Autodesk Fusion 360 part; units mm, degrees
(part 10 of 28)
  line L1869 (14.8547, 52.7364) -> (16.7828, 50.8083)
  line L1870 (16.7828, 50.8083) -> (30.5431, 50.8083)
  line L1871 (30.5431, 50.8083) -> (36.2449, 56.5101)
  line L1872 (36.2449, 56.5101) -> (36.2449, 62.5902)
  line L1873 (36.2449, 62.5902) -> (33.8607, 64.9744)
  line L1874 (33.8607, 64.9744) -> (31.4901, 64.9744)
  line L1875 (31.4901, 64.9744) -> (31.4117, 64.9795)
  line L1876 (31.4117, 64.9795) -> (31.2605, 65.02)
  line L1877 (31.2605, 65.02) -> (31.1248, 65.0984)
  line L1878 (31.1248, 65.0984) -> (31.0658, 65.1501)
  line L1879 (31.0658, 65.1501) -> (28.9704, 67.2455)
  line L1880 (28.9704, 67.2455) -> (28.9187, 67.3045)
  line L1881 (28.9187, 67.3045) -> (28.8404, 67.4401)
  line L1882 (28.8404, 67.4401) -> (28.7998, 67.5914)
  line L1883 (28.7998, 67.5914) -> (28.7947, 67.6697)
  line L1884 (28.7947, 67.6697) -> (28.7947, 69.2413)
  line L1885 (28.7947, 69.2413) -> (28.7998, 69.3196)
  line L1886 (28.7998, 69.3196) -> (28.8404, 69.4709)
  line L1887 (28.8404, 69.4709) -> (28.8416, 69.473)
  line L1888 (28.8416, 69.473) -> (28.8416, 73.4443)
  line L1889 (28.8416, 73.4443) -> (28.8072, 73.4673)
  line L1890 (28.8072, 73.4673) -> (28.6686, 73.6059)
  line L1891 (28.6686, 73.6059) -> (28.5597, 73.7689)
  line L1892 (28.5597, 73.7689) -> (28.4847, 73.95)
  line L1893 (28.4847, 73.95) -> (28.4464, 74.1423)
  line L1894 (28.4464, 74.1423) -> (28.4416, 74.2403)
  line L1895 (28.4416, 74.2403) -> (28.4416, 75.4403)
  line L1896 (28.4416, 75.4403) -> (28.4464, 75.5383)
  line L1897 (28.4464, 75.5383) -> (28.4847, 75.7306)
  line L1898 (28.4847, 75.7306) -> (28.5597, 75.9117)
  line L1899 (28.5597, 75.9117) -> (28.6686, 76.0747)
  line L1900 (28.6686, 76.0747) -> (28.8072, 76.2133)
  line L1901 (28.8072, 76.2133) -> (28.9702, 76.3222)
  line L1902 (28.9702, 76.3222) -> (29.1513, 76.3972)
  line L1903 (29.1513, 76.3972) -> (29.3436, 76.4355)
  line L1904 (29.3436, 76.4355) -> (29.5396, 76.4355)
  line L1905 (29.5396, 76.4355) -> (29.7319, 76.3972)
  line L1906 (29.7319, 76.3972) -> (29.913, 76.3222)
  line L1907 (29.913, 76.3222) -> (30.0101, 76.2573)
  line L1908 (30.0101, 76.2573) -> (32.9677, 79.2149)
  line L1909 (32.9677, 79.2149) -> (32.9677, 83.0947)
  line L1910 (32.9677, 83.0947) -> (32.9146, 83.1217)
  line L1911 (32.9146, 83.1217) -> (32.7559, 83.237)
  line L1912 (32.7559, 83.237) -> (32.6172, 83.3757)
  line L1913 (32.6172, 83.3757) -> (32.5019, 83.5344)
  line L1914 (32.5019, 83.5344) -> (32.4128, 83.7092)
  line L1915 (32.4128, 83.7092) -> (32.3522, 83.8957)
  line L1916 (32.3522, 83.8957) -> (32.3215, 84.0895)
  line L1917 (32.3215, 84.0895) -> (32.3177, 84.1875)
  line L1918 (32.3177, 84.1875) -> (32.3177, 84.6875)
  line L1919 (32.3177, 84.6875) -> (32.3215, 84.7856)
  line L1920 (32.3215, 84.7856) -> (32.3522, 84.9793)
  line L1921 (32.3522, 84.9793) -> (32.4128, 85.1659)
  line L1922 (32.4128, 85.1659) -> (32.5019, 85.3407)
  line L1923 (32.5019, 85.3407) -> (32.6172, 85.4993)
  line L1924 (32.6172, 85.4993) -> (32.7559, 85.638)
  line L1925 (32.7559, 85.638) -> (32.9146, 85.7533)
  line L1926 (32.9146, 85.7533) -> (33.0893, 85.8424)
  line L1927 (33.0893, 85.8424) -> (33.2759, 85.903)
  line L1928 (33.2759, 85.903) -> (33.4696, 85.9337)
  line L1929 (33.4696, 85.9337) -> (33.6658, 85.9337)
  line L1930 (33.6658, 85.9337) -> (33.8595, 85.903)
  line L1931 (68.7845, 85.903) -> (68.971, 85.8424)
  line L1932 (68.971, 85.8424) -> (69.1458, 85.7533)
  line L1933 (69.1458, 85.7533) -> (69.3045, 85.638)
  line L1934 (69.3045, 85.638) -> (69.4432, 85.4993)
  line L1935 (69.4432, 85.4993) -> (69.5585, 85.3407)
  line L1936 (69.5585, 85.3407) -> (69.6475, 85.1659)
  line L1937 (69.6475, 85.1659) -> (69.7082, 84.9793)
  line L1938 (69.7082, 84.9793) -> (69.7388, 84.7856)
  line L1939 (69.7388, 84.7856) -> (69.7427, 84.6875)
  line L1940 (69.7427, 84.6875) -> (69.7427, 84.1875)
  line L1941 (69.7427, 84.1875) -> (69.7388, 84.0895)
  line L1942 (69.7388, 84.0895) -> (69.7082, 83.8957)
  line L1943 (69.7082, 83.8957) -> (69.6475, 83.7092)
  line L1944 (69.6475, 83.7092) -> (69.5585, 83.5344)
  line L1945 (69.5585, 83.5344) -> (69.4432, 83.3757)
  line L1946 (69.4432, 83.3757) -> (69.3045, 83.237)
  line L1947 (69.3045, 83.237) -> (69.1458, 83.1217)
  line L1948 (69.1458, 83.1217) -> (69.0927, 83.0947)
  line L1949 (69.0927, 83.0947) -> (69.0927, 78.9664)
  line L1950 (69.0927, 78.9664) -> (69.0876, 78.8881)
  line L1951 (69.0876, 78.8881) -> (69.047, 78.7368)
  line L1952 (69.047, 78.7368) -> (68.9687, 78.6011)
  line L1953 (68.9687, 78.6011) -> (68.917, 78.5421)
  line L1954 (68.917, 78.5421) -> (65.3666, 74.9918)
  line L1955 (65.3666, 74.9918) -> (65.3666, 74.2403)
  line L1956 (65.3666, 74.2403) -> (65.3618, 74.1423)
  line L1957 (65.3618, 74.1423) -> (65.3235, 73.95)
  line L1958 (65.3235, 73.95) -> (65.2485, 73.7689)
  line L1959 (65.2485, 73.7689) -> (65.1396, 73.6059)
  line L1960 (65.1396, 73.6059) -> (65.001, 73.4673)
  line L1961 (65.001, 73.4673) -> (64.9666, 73.4443)
  line L1962 (64.9666, 73.4443) -> (64.9666, 69.2882)
  line L1963 (64.9666, 69.2882) -> (64.9615, 69.2098)
  line L1964 (64.9615, 69.2098) -> (64.9259, 69.077)
  line L1965 (64.9259, 69.077) -> (64.9209, 69.0586)
  line L1966 (64.9209, 69.0586) -> (64.9197, 69.0564)
  line L1967 (64.9197, 69.0564) -> (64.9197, 67.9183)
  line L1968 (64.9197, 67.9183) -> (66.6636, 66.1744)
  line L1969 (66.6636, 66.1744) -> (69.0343, 66.1744)
  line L1970 (69.0343, 66.1744) -> (69.1126, 66.1692)
  line L1971 (69.1126, 66.1692) -> (69.2639, 66.1287)
  line L1972 (69.2639, 66.1287) -> (69.3995, 66.0504)
  line L1973 (69.3995, 66.0504) -> (69.4585, 65.9986)
  line L1974 (69.4585, 65.9986) -> (72.1942, 63.263)
  line L1975 (72.1942, 63.263) -> (72.2459, 63.204)
  line L1976 (72.2459, 63.204) -> (72.3242, 63.0683)
  line L1977 (72.3242, 63.0683) -> (72.3648, 62.9171)
  line L1978 (72.3648, 62.9171) -> (72.3699, 62.8387)
  line L1979 (72.3699, 62.8387) -> (72.3699, 56.2616)
  line L1980 (72.3699, 56.2616) -> (72.3648, 56.1833)
  line L1981 (72.3648, 56.1833) -> (72.3242, 56.032)
  line L1982 (72.3242, 56.032) -> (72.2459, 55.8963)
  line L1983 (72.2459, 55.8963) -> (72.1942, 55.8373)
  line L1984 (72.1942, 55.8373) -> (66.1409, 49.784)
  line L1985 (66.1409, 49.784) -> (66.0819, 49.7323)
  line L1986 (66.0819, 49.7323) -> (65.9462, 49.654)
  line L1987 (65.9462, 49.654) -> (65.7949, 49.6134)
  line L1988 (65.7949, 49.6134) -> (65.7166, 49.6083)
  line L1989 (65.7166, 49.6083) -> (51.4593, 49.6083)
  line L1990 (51.4593, 49.6083) -> (51.381, 49.6134)
  line L1991 (51.381, 49.6134) -> (51.2297, 49.654)
  line L1992 (51.2297, 49.654) -> (51.094, 49.7323)
  line L1993 (51.094, 49.7323) -> (51.035, 49.784)
  line L1994 (51.035, 49.784) -> (48.566, 52.2531)
  line L1995 (48.566, 52.2531) -> (47.7125, 52.2531)
  line L1996 (47.7125, 52.2531) -> (47.6033, 52.269)
  line L1997 (47.6033, 52.269) -> (47.4901, 52.3244)
  line L1998 (47.4901, 52.3244) -> (47.4009, 52.4135)
  line L1999 (47.4009, 52.4135) -> (47.3456, 52.5267)
  line L2000 (47.3456, 52.5267) -> (47.3297, 52.6359)
  line L2001 (47.3297, 52.6359) -> (47.3297, 54.8703)
  line L2002 (47.3297, 54.8703) -> (47.3456, 54.9795)
  line L2003 (47.3456, 54.9795) -> (47.4009, 55.0927)
  line L2004 (47.4009, 55.0927) -> (47.4901, 55.1819)
  line L2005 (47.4901, 55.1819) -> (47.6033, 55.2372)
  line L2006 (47.6033, 55.2372) -> (47.7125, 55.2531)
  line L2007 (47.7125, 55.2531) -> (49.3969, 55.2531)
  line L2008 (49.3969, 55.2531) -> (49.5061, 55.2372)
  line L2009 (49.5061, 55.2372) -> (49.6193, 55.1819)
  line L2010 (49.6193, 55.1819) -> (49.7084, 55.0927)
  line L2011 (49.7084, 55.0927) -> (49.7638, 54.9795)
  line L2012 (49.7638, 54.9795) -> (49.7797, 54.8703)
  line L2013 (49.7797, 54.8703) -> (49.7797, 52.7364)
  line L2014 (49.7797, 52.7364) -> (51.7078, 50.8083)
  line L2015 (51.7078, 50.8083) -> (65.4681, 50.8083)
  line L2016 (65.4681, 50.8083) -> (71.1699, 56.5101)
  line L2017 (71.1699, 56.5101) -> (71.1699, 62.5902)
  line L2018 (71.1699, 62.5902) -> (68.7858, 64.9744)
  line L2019 (68.7858, 64.9744) -> (66.4151, 64.9744)
  line L2020 (66.4151, 64.9744) -> (66.3367, 64.9795)
  line L2021 (66.3367, 64.9795) -> (66.1855, 65.02)
  line L2022 (66.1855, 65.02) -> (66.0498, 65.0984)
  line L2023 (66.0498, 65.0984) -> (65.9908, 65.1501)
  line L2024 (65.9908, 65.1501) -> (63.8954, 67.2455)
  line L2025 (63.8954, 67.2455) -> (63.8437, 67.3045)
  line L2026 (63.8437, 67.3045) -> (63.7654, 67.4401)
  line L2027 (63.7654, 67.4401) -> (63.7248, 67.5914)
  line L2028 (63.7248, 67.5914) -> (63.7197, 67.6697)
  line L2029 (63.7197, 67.6697) -> (63.7197, 69.2413)
  line L2030 (63.7197, 69.2413) -> (63.7248, 69.3196)
  line L2031 (63.7248, 69.3196) -> (63.7654, 69.4709)
  line L2032 (63.7654, 69.4709) -> (63.7666, 69.473)
  line L2033 (63.7666, 69.473) -> (63.7666, 73.4443)
  line L2034 (63.7666, 73.4443) -> (63.7322, 73.4673)
  line L2035 (63.7322, 73.4673) -> (63.5936, 73.6059)
  line L2036 (63.5936, 73.6059) -> (63.4847, 73.7689)
  line L2037 (63.4847, 73.7689) -> (63.4097, 73.95)
  line L2038 (63.4097, 73.95) -> (63.3714, 74.1423)
  line L2039 (63.3714, 74.1423) -> (63.3666, 74.2403)
  line L2040 (63.3666, 74.2403) -> (63.3666, 75.4403)
  line L2041 (63.3666, 75.4403) -> (63.3714, 75.5383)
  line L2042 (63.3714, 75.5383) -> (63.4097, 75.7306)
  line L2043 (63.4097, 75.7306) -> (63.4847, 75.9117)
  line L2044 (63.4847, 75.9117) -> (63.5936, 76.0747)
  line L2045 (63.5936, 76.0747) -> (63.7322, 76.2133)
  line L2046 (63.7322, 76.2133) -> (63.8952, 76.3222)
  line L2047 (63.8952, 76.3222) -> (64.0763, 76.3972)
  line L2048 (64.0763, 76.3972) -> (64.2686, 76.4355)
  line L2049 (64.2686, 76.4355) -> (64.4646, 76.4355)
  line L2050 (64.4646, 76.4355) -> (64.6569, 76.3972)
  line L2051 (64.6569, 76.3972) -> (64.838, 76.3222)
  line L2052 (64.838, 76.3222) -> (64.9351, 76.2573)
  line L2053 (64.9351, 76.2573) -> (67.8927, 79.2149)
  line L2054 (67.8927, 79.2149) -> (67.8927, 83.0947)
  line L2055 (67.8927, 83.0947) -> (67.8396, 83.1217)
  line L2056 (67.8396, 83.1217) -> (67.6809, 83.237)
  line L2057 (67.6809, 83.237) -> (67.5422, 83.3757)
  line L2058 (67.5422, 83.3757) -> (67.4269, 83.5344)
  line L2059 (67.4269, 83.5344) -> (67.3378, 83.7092)
  line L2060 (67.3378, 83.7092) -> (67.2772, 83.8957)
  line L2061 (67.2772, 83.8957) -> (67.2465, 84.0895)
  line L2062 (67.2465, 84.0895) -> (67.2427, 84.1875)
  line L2063 (67.2427, 84.1875) -> (67.2427, 84.6875)
  line L2064 (67.2427, 84.6875) -> (67.2465, 84.7856)
  line L2065 (67.2465, 84.7856) -> (67.2772, 84.9793)
  line L2066 (67.2772, 84.9793) -> (67.3378, 85.1659)
  line L2067 (67.3378, 85.1659) -> (67.4269, 85.3407)
  line L2068 (67.4269, 85.3407) -> (67.5422, 85.4993)
  line L2069 (67.5422, 85.4993) -> (67.6809, 85.638)
  line L2070 (67.6809, 85.638) -> (67.8396, 85.7533)
  line L2071 (67.8396, 85.7533) -> (68.0143, 85.8424)
  line L2072 (68.0143, 85.8424) -> (68.2009, 85.903)
  line L2073 (68.2009, 85.903) -> (68.3946, 85.9337)
  line L2074 (68.3946, 85.9337) -> (68.5908, 85.9337)
  line L2075 (68.5908, 85.9337) -> (68.7845, 85.903)
  line L2076 (103.7095, 85.903) -> (103.896, 85.8424)
  line L2077 (103.896, 85.8424) -> (104.0708, 85.7533)
  line L2078 (104.0708, 85.7533) -> (104.2295, 85.638)
  line L2079 (104.2295, 85.638) -> (104.3682, 85.4993)
  line L2080 (104.3682, 85.4993) -> (104.4835, 85.3407)
  line L2081 (104.4835, 85.3407) -> (104.5725, 85.1659)
  line L2082 (104.5725, 85.1659) -> (104.6332, 84.9793)
  line L2083 (104.6332, 84.9793) -> (104.6638, 84.7856)
  line L2084 (104.6638, 84.7856) -> (104.6677, 84.6875)
  line L2085 (104.6677, 84.6875) -> (104.6677, 84.1875)
  line L2086 (104.6677, 84.1875) -> (104.6638, 84.0895)
  line L2087 (104.6638, 84.0895) -> (104.6332, 83.8957)
  line L2088 (104.6332, 83.8957) -> (104.5725, 83.7092)
  line L2089 (104.5725, 83.7092) -> (104.4835, 83.5344)
  line L2090 (104.4835, 83.5344) -> (104.3682, 83.3757)
  line L2091 (104.3682, 83.3757) -> (104.2295, 83.237)
  line L2092 (104.2295, 83.237) -> (104.0708, 83.1217)
  line L2093 (104.0708, 83.1217) -> (104.0177, 83.0947)
  line L2094 (104.0177, 83.0947) -> (104.0177, 78.9664)
  line L2095 (104.0177, 78.9664) -> (104.0126, 78.8881)
  line L2096 (104.0126, 78.8881) -> (103.972, 78.7368)
  line L2097 (103.972, 78.7368) -> (103.8937, 78.6011)
  line L2098 (103.8937, 78.6011) -> (103.842, 78.5421)
  line L2099 (103.842, 78.5421) -> (100.2916, 74.9918)
  line L2100 (100.2916, 74.9918) -> (100.2916, 74.2403)
  line L2101 (100.2916, 74.2403) -> (100.2868, 74.1423)
  line L2102 (100.2868, 74.1423) -> (100.2485, 73.95)
  line L2103 (100.2485, 73.95) -> (100.1735, 73.7689)
  line L2104 (100.1735, 73.7689) -> (100.0646, 73.6059)
  line L2105 (100.0646, 73.6059) -> (99.926, 73.4673)
  line L2106 (99.926, 73.4673) -> (99.8916, 73.4443)
  line L2107 (99.8916, 73.4443) -> (99.8916, 69.2882)
  line L2108 (99.8916, 69.2882) -> (99.8865, 69.2098)
  line L2109 (99.8865, 69.2098) -> (99.8509, 69.077)
  line L2110 (99.8509, 69.077) -> (99.8459, 69.0586)
  line L2111 (99.8459, 69.0586) -> (99.8447, 69.0564)
  line L2112 (99.8447, 69.0564) -> (99.8447, 67.9183)
  line L2113 (99.8447, 67.9183) -> (101.5886, 66.1744)
  line L2114 (101.5886, 66.1744) -> (103.9593, 66.1744)
  line L2115 (103.9593, 66.1744) -> (104.0376, 66.1692)
  line L2116 (104.0376, 66.1692) -> (104.1889, 66.1287)
  line L2117 (104.1889, 66.1287) -> (104.3245, 66.0504)
  line L2118 (104.3245, 66.0504) -> (104.3835, 65.9986)
  line L2119 (104.3835, 65.9986) -> (107.1192, 63.263)
  line L2120 (107.1192, 63.263) -> (107.1709, 63.204)
  line L2121 (107.1709, 63.204) -> (107.2492, 63.0683)
  line L2122 (107.2492, 63.0683) -> (107.2898, 62.9171)
  line L2123 (107.2898, 62.9171) -> (107.2949, 62.8387)
  line L2124 (107.2949, 62.8387) -> (107.2949, 56.2616)
  line L2125 (107.2949, 56.2616) -> (107.2898, 56.1833)
  line L2126 (107.2898, 56.1833) -> (107.2492, 56.032)
  line L2127 (107.2492, 56.032) -> (107.1709, 55.8963)
  line L2128 (107.1709, 55.8963) -> (107.1192, 55.8373)
  line L2129 (107.1192, 55.8373) -> (101.0659, 49.784)
  line L2130 (101.0659, 49.784) -> (101.0069, 49.7323)
  line L2131 (101.0069, 49.7323) -> (100.8712, 49.654)
  line L2132 (100.8712, 49.654) -> (100.7199, 49.6134)
  line L2133 (100.7199, 49.6134) -> (100.6416, 49.6083)
  line L2134 (100.6416, 49.6083) -> (86.3843, 49.6083)
  line L2135 (86.3843, 49.6083) -> (86.306, 49.6134)
  line L2136 (86.306, 49.6134) -> (86.1547, 49.654)
  line L2137 (86.1547, 49.654) -> (86.019, 49.7323)
  line L2138 (86.019, 49.7323) -> (85.96, 49.784)
  line L2139 (85.96, 49.784) -> (83.491, 52.2531)
  line L2140 (83.491, 52.2531) -> (82.6375, 52.2531)
  line L2141 (82.6375, 52.2531) -> (82.5283, 52.269)
  line L2142 (82.5283, 52.269) -> (82.4151, 52.3244)
  line L2143 (82.4151, 52.3244) -> (82.3259, 52.4135)
  line L2144 (82.3259, 52.4135) -> (82.2706, 52.5267)
  line L2145 (82.2706, 52.5267) -> (82.2547, 52.6359)
  line L2146 (82.2547, 52.6359) -> (82.2547, 54.8703)
  line L2147 (82.2547, 54.8703) -> (82.2706, 54.9795)
  line L2148 (82.2706, 54.9795) -> (82.3259, 55.0927)
  line L2149 (82.3259, 55.0927) -> (82.4151, 55.1819)
  line L2150 (82.4151, 55.1819) -> (82.5283, 55.2372)
  line L2151 (82.5283, 55.2372) -> (82.6375, 55.2531)
  line L2152 (82.6375, 55.2531) -> (84.3219, 55.2531)
  line L2153 (84.3219, 55.2531) -> (84.4311, 55.2372)
  line L2154 (84.4311, 55.2372) -> (84.5443, 55.1819)
  line L2155 (84.5443, 55.1819) -> (84.6334, 55.0927)
  line L2156 (84.6334, 55.0927) -> (84.6888, 54.9795)
  line L2157 (84.6888, 54.9795) -> (84.7047, 54.8703)
  line L2158 (84.7047, 54.8703) -> (84.7047, 52.7364)
  line L2159 (84.7047, 52.7364) -> (86.6328, 50.8083)
  line L2160 (86.6328, 50.8083) -> (100.3931, 50.8083)
  line L2161 (100.3931, 50.8083) -> (106.0949, 56.5101)
  line L2162 (106.0949, 56.5101) -> (106.0949, 62.5902)
  line L2163 (106.0949, 62.5902) -> (103.7108, 64.9744)
  line L2164 (103.7107, 64.9744) -> (101.3401, 64.9744)
  line L2165 (101.3401, 64.9744) -> (101.2617, 64.9795)
  line L2166 (101.2617, 64.9795) -> (101.1105, 65.02)
  line L2167 (101.1105, 65.02) -> (100.9748, 65.0984)
  line L2168 (100.9748, 65.0984) -> (100.9158, 65.1501)
  line L2169 (100.9158, 65.1501) -> (98.8204, 67.2455)
  line L2170 (98.8204, 67.2455) -> (98.7687, 67.3045)
  line L2171 (98.7687, 67.3045) -> (98.6904, 67.4401)
  line L2172 (98.6904, 67.4401) -> (98.6498, 67.5914)
  line L2173 (98.6498, 67.5914) -> (98.6447, 67.6697)
  line L2174 (98.6447, 67.6697) -> (98.6447, 69.2413)
  line L2175 (98.6447, 69.2413) -> (98.6498, 69.3196)
  line L2176 (98.6498, 69.3196) -> (98.6904, 69.4709)
  line L2177 (98.6904, 69.4709) -> (98.6916, 69.473)
  line L2178 (98.6916, 69.473) -> (98.6916, 73.4443)
  line L2179 (98.6916, 73.4443) -> (98.6572, 73.4673)
  line L2180 (98.6572, 73.4673) -> (98.5186, 73.6059)
  line L2181 (98.5186, 73.6059) -> (98.4097, 73.7689)
  line L2182 (98.4097, 73.7689) -> (98.3347, 73.95)
  line L2183 (98.3347, 73.95) -> (98.2964, 74.1423)
  line L2184 (98.2964, 74.1423) -> (98.2916, 74.2403)
  line L2185 (98.2916, 74.2403) -> (98.2916, 75.4403)
  line L2186 (98.2916, 75.4403) -> (98.2964, 75.5383)
  line L2187 (98.2964, 75.5383) -> (98.3347, 75.7306)
  line L2188 (98.3347, 75.7306) -> (98.4097, 75.9117)
  line L2189 (98.4097, 75.9117) -> (98.5186, 76.0747)
  line L2190 (98.5186, 76.0747) -> (98.6572, 76.2133)
  line L2191 (98.6572, 76.2133) -> (98.8202, 76.3222)
  line L2192 (98.8202, 76.3222) -> (99.0013, 76.3972)
  line L2193 (99.0013, 76.3972) -> (99.1936, 76.4355)
  line L2194 (99.1936, 76.4355) -> (99.3896, 76.4355)
  line L2195 (99.3896, 76.4355) -> (99.5819, 76.3972)
  line L2196 (99.5819, 76.3972) -> (99.763, 76.3222)
  line L2197 (99.763, 76.3222) -> (99.8601, 76.2573)
  line L2198 (99.8601, 76.2573) -> (102.8177, 79.2149)
  line L2199 (102.8177, 79.2149) -> (102.8177, 83.0947)
  line L2200 (102.8177, 83.0947) -> (102.7646, 83.1217)
  line L2201 (102.7646, 83.1217) -> (102.6059, 83.237)
  line L2202 (102.6059, 83.237) -> (102.4672, 83.3757)
  line L2203 (102.4672, 83.3757) -> (102.3519, 83.5344)
  line L2204 (102.3519, 83.5344) -> (102.2628, 83.7092)
  line L2205 (102.2628, 83.7092) -> (102.2022, 83.8957)
  line L2206 (102.2022, 83.8957) -> (102.1715, 84.0895)
  line L2207 (102.1715, 84.0895) -> (102.1677, 84.1875)
  line L2208 (102.1677, 84.1875) -> (102.1677, 84.6875)
  line L2209 (102.1677, 84.6875) -> (102.1715, 84.7856)
  line L2210 (102.1715, 84.7856) -> (102.2022, 84.9793)
  line L2211 (102.2022, 84.9793) -> (102.2628, 85.1659)
  line L2212 (102.2628, 85.1659) -> (102.3519, 85.3407)
  line L2213 (102.3519, 85.3407) -> (102.4672, 85.4993)
  line L2214 (102.4672, 85.4993) -> (102.6059, 85.638)
  line L2215 (102.6059, 85.638) -> (102.7646, 85.7533)
  line L2216 (102.7646, 85.7533) -> (102.9393, 85.8424)
  line L2217 (102.9393, 85.8424) -> (103.1259, 85.903)
  line L2218 (103.1259, 85.903) -> (103.3196, 85.9337)
  line L2219 (103.3196, 85.9337) -> (103.5158, 85.9337)
  line L2220 (103.5158, 85.9337) -> (103.7095, 85.903)
  line L2221 (138.6345, 85.903) -> (138.821, 85.8424)
  line L2222 (138.821, 85.8424) -> (138.9958, 85.7533)
  line L2223 (138.9958, 85.7533) -> (139.1545, 85.638)
  line L2224 (139.1545, 85.638) -> (139.2932, 85.4993)
  line L2225 (139.2932, 85.4993) -> (139.4085, 85.3407)
  line L2226 (139.4085, 85.3407) -> (139.4975, 85.1659)
  line L2227 (139.4975, 85.1659) -> (139.5582, 84.9793)
  line L2228 (139.5582, 84.9793) -> (139.5888, 84.7856)
  line L2229 (139.5888, 84.7856) -> (139.5927, 84.6875)
  line L2230 (139.5927, 84.6875) -> (139.5927, 84.1875)
  line L2231 (139.5927, 84.1875) -> (139.5888, 84.0895)
  line L2232 (139.5888, 84.0895) -> (139.5582, 83.8957)
  line L2233 (139.5582, 83.8957) -> (139.4975, 83.7092)
  line L2234 (139.4975, 83.7092) -> (139.4085, 83.5344)
  line L2235 (139.4085, 83.5344) -> (139.2932, 83.3757)
  line L2236 (139.2932, 83.3757) -> (139.1545, 83.237)
  line L2237 (139.1545, 83.237) -> (138.9958, 83.1217)
  line L2238 (138.9958, 83.1217) -> (138.9427, 83.0947)
  line L2239 (138.9427, 83.0947) -> (138.9427, 78.9664)
  line L2240 (138.9427, 78.9664) -> (138.9376, 78.8881)
  line L2241 (138.9376, 78.8881) -> (138.897, 78.7368)
  line L2242 (138.897, 78.7368) -> (138.8187, 78.6011)
  line L2243 (138.8187, 78.6011) -> (138.767, 78.5421)
  line L2244 (138.767, 78.5421) -> (135.2166, 74.9918)
  line L2245 (135.2166, 74.9918) -> (135.2166, 74.2403)
  line L2246 (135.2166, 74.2403) -> (135.2118, 74.1423)
  line L2247 (135.2118, 74.1423) -> (135.1735, 73.95)
  line L2248 (135.1735, 73.95) -> (135.0985, 73.7689)
  line L2249 (135.0985, 73.7689) -> (134.9896, 73.6059)
  line L2250 (134.9896, 73.6059) -> (134.851, 73.4673)
  line L2251 (134.851, 73.4673) -> (134.8166, 73.4443)
  line L2252 (134.8166, 73.4443) -> (134.8166, 69.2882)
  line L2253 (134.8166, 69.2882) -> (134.8115, 69.2098)
  line L2254 (134.8115, 69.2098) -> (134.7759, 69.077)
  line L2255 (134.7759, 69.077) -> (134.7709, 69.0586)
  line L2256 (134.7709, 69.0586) -> (134.7697, 69.0564)
  line L2257 (134.7697, 69.0564) -> (134.7697, 67.9183)
  line L2258 (134.7697, 67.9183) -> (136.5136, 66.1744)
  line L2259 (136.5136, 66.1744) -> (138.8843, 66.1744)
  line L2260 (138.8843, 66.1744) -> (138.9626, 66.1692)
  line L2261 (138.9626, 66.1692) -> (139.1139, 66.1287)
  line L2262 (139.1139, 66.1287) -> (139.2495, 66.0504)
  line L2263 (139.2495, 66.0504) -> (139.3085, 65.9986)
  line L2264 (139.3085, 65.9986) -> (142.0442, 63.263)
  line L2265 (142.0442, 63.263) -> (142.0959, 63.204)
  line L2266 (142.0959, 63.204) -> (142.1742, 63.0683)
  line L2267 (142.1742, 63.0683) -> (142.2148, 62.9171)
  line L2268 (142.2148, 62.9171) -> (142.2199, 62.8387)
  line L2269 (142.2199, 62.8387) -> (142.2199, 56.2616)
  line L2270 (142.2199, 56.2616) -> (142.2148, 56.1833)
  line L2271 (142.2148, 56.1833) -> (142.1742, 56.032)
  line L2272 (142.1742, 56.032) -> (142.0959, 55.8963)
  line L2273 (142.0959, 55.8963) -> (142.0442, 55.8373)
  line L2274 (142.0442, 55.8373) -> (135.9909, 49.784)
  line L2275 (135.9909, 49.784) -> (135.9319, 49.7323)
  line L2276 (135.9319, 49.7323) -> (135.7962, 49.654)
  line L2277 (135.7962, 49.654) -> (135.6449, 49.6134)
  line L2278 (135.6449, 49.6134) -> (135.5666, 49.6083)
  line L2279 (135.5666, 49.6083) -> (121.3093, 49.6083)
  line L2280 (121.3093, 49.6083) -> (121.231, 49.6134)
  line L2281 (121.231, 49.6134) -> (121.0797, 49.654)
  line L2282 (121.0797, 49.654) -> (120.944, 49.7323)
  line L2283 (120.944, 49.7323) -> (120.885, 49.784)
  line L2284 (120.885, 49.784) -> (118.416, 52.2531)
  line L2285 (118.416, 52.2531) -> (117.5625, 52.2531)
  line L2286 (117.5625, 52.2531) -> (117.4533, 52.269)
  line L2287 (117.4533, 52.269) -> (117.3401, 52.3244)
  line L2288 (117.3401, 52.3244) -> (117.2509, 52.4135)
  line L2289 (117.2509, 52.4135) -> (117.1956, 52.5267)
  line L2290 (117.1956, 52.5267) -> (117.1797, 52.6359)
  line L2291 (117.1797, 52.6359) -> (117.1797, 54.8703)
  line L2292 (117.1797, 54.8703) -> (117.1956, 54.9795)
  line L2293 (117.1956, 54.9795) -> (117.2509, 55.0927)
  line L2294 (117.2509, 55.0927) -> (117.3401, 55.1819)
  line L2295 (117.3401, 55.1819) -> (117.4533, 55.2372)
  line L2296 (117.4533, 55.2372) -> (117.5625, 55.2531)
  line L2297 (117.5625, 55.2531) -> (119.2469, 55.2531)
  line L2298 (119.2469, 55.2531) -> (119.3561, 55.2372)
  line L2299 (119.3561, 55.2372) -> (119.4693, 55.1819)
  line L2300 (119.4693, 55.1819) -> (119.5584, 55.0927)
  line L2301 (119.5584, 55.0927) -> (119.6138, 54.9795)
  line L2302 (119.6138, 54.9795) -> (119.6297, 54.8703)
  line L2303 (119.6297, 54.8703) -> (119.6297, 52.7364)
  line L2304 (119.6297, 52.7364) -> (121.5578, 50.8083)
  line L2305 (121.5578, 50.8083) -> (135.3181, 50.8083)
  line L2306 (135.3181, 50.8083) -> (141.0199, 56.5101)
  line L2307 (141.0199, 56.5101) -> (141.0199, 62.5902)
  line L2308 (141.0199, 62.5902) -> (138.6357, 64.9744)
  line L2309 (138.6357, 64.9744) -> (136.2651, 64.9744)
  line L2310 (136.2651, 64.9744) -> (136.1867, 64.9795)
  line L2311 (136.1867, 64.9795) -> (136.0355, 65.02)
  line L2312 (136.0355, 65.02) -> (135.8998, 65.0984)
  line L2313 (135.8998, 65.0984) -> (135.8408, 65.1501)
  line L2314 (135.8408, 65.1501) -> (133.7454, 67.2455)
  line L2315 (133.7454, 67.2455) -> (133.6937, 67.3045)
  line L2316 (133.6937, 67.3045) -> (133.6154, 67.4401)
  line L2317 (133.6154, 67.4401) -> (133.5748, 67.5914)
  line L2318 (133.5748, 67.5914) -> (133.5697, 67.6697)
  line L2319 (133.5697, 67.6697) -> (133.5697, 69.2413)
  line L2320 (133.5697, 69.2413) -> (133.5748, 69.3196)
  line L2321 (133.5748, 69.3196) -> (133.6154, 69.4709)
  line L2322 (133.6154, 69.4709) -> (133.6166, 69.473)
  line L2323 (133.6166, 69.473) -> (133.6166, 73.4443)
  line L2324 (133.6166, 73.4443) -> (133.5822, 73.4673)
  line L2325 (133.5822, 73.4673) -> (133.4436, 73.6059)
  line L2326 (133.4436, 73.6059) -> (133.3347, 73.7689)
  line L2327 (133.3347, 73.7689) -> (133.2597, 73.95)
  line L2328 (133.2597, 73.95) -> (133.2214, 74.1423)
  line L2329 (133.2214, 74.1423) -> (133.2166, 74.2403)
  line L2330 (133.2166, 74.2403) -> (133.2166, 75.4403)
  line L2331 (133.2166, 75.4403) -> (133.2214, 75.5383)
  line L2332 (133.2214, 75.5383) -> (133.2597, 75.7306)
  line L2333 (133.2597, 75.7306) -> (133.3347, 75.9117)
  line L2334 (133.3347, 75.9117) -> (133.4436, 76.0747)
  line L2335 (133.4436, 76.0747) -> (133.5822, 76.2133)
  line L2336 (133.5822, 76.2133) -> (133.7452, 76.3222)
  line L2337 (133.7452, 76.3222) -> (133.9263, 76.3972)
  line L2338 (133.9263, 76.3972) -> (134.1186, 76.4355)
  line L2339 (134.1186, 76.4355) -> (134.3146, 76.4355)
  line L2340 (134.3146, 76.4355) -> (134.5069, 76.3972)
  line L2341 (134.5069, 76.3972) -> (134.688, 76.3222)
  line L2342 (134.688, 76.3222) -> (134.7851, 76.2573)
  line L2343 (134.7851, 76.2573) -> (137.7427, 79.2149)
  line L2344 (137.7427, 79.2149) -> (137.7427, 83.0947)
  line L2345 (137.7427, 83.0947) -> (137.6896, 83.1217)
  line L2346 (137.6896, 83.1217) -> (137.5309, 83.237)
  line L2347 (137.5309, 83.237) -> (137.3922, 83.3757)
  line L2348 (137.3922, 83.3757) -> (137.2769, 83.5344)
  line L2349 (137.2769, 83.5344) -> (137.1878, 83.7092)
  line L2350 (137.1878, 83.7092) -> (137.1272, 83.8957)
  line L2351 (137.1272, 83.8957) -> (137.0965, 84.0895)
  line L2352 (137.0965, 84.0895) -> (137.0927, 84.1875)
  line L2353 (137.0927, 84.1875) -> (137.0927, 84.6875)
  line L2354 (137.0927, 84.6875) -> (137.0965, 84.7856)
  line L2355 (137.0965, 84.7856) -> (137.1272, 84.9793)
  line L2356 (137.1272, 84.9793) -> (137.1878, 85.1659)
  line L2357 (137.1878, 85.1659) -> (137.2769, 85.3407)
  line L2358 (137.2769, 85.3407) -> (137.3922, 85.4993)
  line L2359 (137.3922, 85.4993) -> (137.5309, 85.638)
  line L2360 (137.5309, 85.638) -> (137.6896, 85.7533)
  line L2361 (137.6896, 85.7533) -> (137.8643, 85.8424)
  line L2362 (137.8643, 85.8424) -> (138.0509, 85.903)
  line L2363 (138.0509, 85.903) -> (138.2446, 85.9337)
  line L2364 (138.2446, 85.9337) -> (138.4408, 85.9337)
  line L2365 (138.4408, 85.9337) -> (138.6345, 85.903)
  line L2366 (24.7524, 89.0733) -> (24.1274, 89.0733)
  line L2367 (24.1274, 89.0733) -> (24.1274, 88.4311)
  line L2368 (24.1274, 88.4311) -> (24.1222, 88.3528)
  line L2369 (24.1222, 88.3528) -> (24.0817, 88.2015)
  line L2370 (24.0817, 88.2015) -> (24.0034, 88.0658)
  line L2371 (24.0034, 88.0658) -> (23.9516, 88.0068)
  line L2372 (23.9516, 88.0068) -> (18.7612, 82.8164)
  line L2373 (18.7612, 82.8164) -> (18.7612, 79.3846)
  line L2374 (18.7612, 79.3846) -> (19.3308, 78.815)
  line L2375 (19.3308, 78.815) -> (19.3825, 78.756)
  line L2376 (19.3825, 78.756) -> (19.4609, 78.6203)
  line L2377 (19.4609, 78.6203) -> (19.4818, 78.5421)
  line L2378 (19.4818, 78.5421) -> (19.5014, 78.469)
  line L2379 (19.5014, 78.469) -> (19.5065, 78.3907)
  line L2380 (19.5065, 78.3907) -> (19.5065, 76.2945)
  line L2381 (19.5065, 76.2945) -> (19.5409, 76.2715)
  line L2382 (19.5409, 76.2715) -> (19.6795, 76.1329)
  line L2383 (19.6795, 76.1329) -> (19.7884, 75.9699)
  line L2384 (19.7884, 75.9699) -> (19.8635, 75.7888)
  line L2385 (19.8635, 75.7888) -> (19.9017, 75.5965)
  line L2386 (19.9017, 75.5965) -> (19.9065, 75.4985)
  line L2387 (19.9065, 75.4985) -> (19.9065, 74.2985)
  line L2388 (19.9065, 74.2985) -> (19.9017, 74.2005)
  line L2389 (19.9017, 74.2005) -> (19.8635, 74.0082)
  line L2390 (19.8635, 74.0082) -> (19.7884, 73.8271)
  line L2391 (19.7884, 73.8271) -> (19.6795, 73.6641)
  line L2392 (19.6795, 73.6641) -> (19.5409, 73.5255)
  line L2393 (19.5409, 73.5255) -> (19.5065, 73.5025)
  line L2394 (19.5065, 73.5025) -> (19.5065, 59.487)
  line L2395 (19.5065, 59.487) -> (24.1535, 54.84)
  line L2396 (24.1535, 54.84) -> (25.6472, 54.84)
  line L2397 (25.6472, 54.84) -> (25.7564, 54.8241)
  line L2398 (25.7564, 54.8241) -> (25.8696, 54.7687)
  line L2399 (25.8696, 54.7687) -> (25.9587, 54.6796)
  line L2400 (25.9587, 54.6796) -> (26.0141, 54.5664)
  line L2401 (26.0141, 54.5664) -> (26.03, 54.4572)
  line L2402 (26.03, 54.4572) -> (26.03, 52.2228)
  line L2403 (26.03, 52.2228) -> (26.0141, 52.1136)
  line L2404 (26.0141, 52.1136) -> (25.9587, 52.0004)
  line L2405 (25.9587, 52.0004) -> (25.8696, 51.9113)
  line L2406 (25.8696, 51.9113) -> (25.7564, 51.8559)
  line L2407 (25.7564, 51.8559) -> (25.6472, 51.84)
  line L2408 (25.6472, 51.84) -> (23.9628, 51.84)
  line L2409 (23.9628, 51.84) -> (23.8536, 51.8559)
  line L2410 (23.8536, 51.8559) -> (23.7404, 51.9113)
  line L2411 (23.7404, 51.9113) -> (23.6513, 52.0004)
  line L2412 (23.6513, 52.0004) -> (23.5959, 52.1136)
  line L2413 (23.5959, 52.1136) -> (23.58, 52.2228)
  line L2414 (23.58, 52.2228) -> (23.58, 53.7165)
  line L2415 (23.58, 53.7165) -> (18.4823, 58.8142)
  line L2416 (18.4823, 58.8142) -> (18.4305, 58.8732)
  line L2417 (18.4305, 58.8732) -> (18.3522, 59.0089)
  line L2418 (18.3522, 59.0089) -> (18.3117, 59.1602)
  line L2419 (18.3117, 59.1602) -> (18.3065, 59.2385)
  line L2420 (18.3065, 59.2385) -> (18.3065, 73.5025)
  line L2421 (18.3065, 73.5025) -> (18.2721, 73.5255)
  line L2422 (18.2721, 73.5255) -> (18.1335, 73.6641)
  line L2423 (18.1335, 73.6641) -> (18.0246, 73.8271)
  line L2424 (18.0246, 73.8271) -> (17.9496, 74.0082)
  line L2425 (17.9496, 74.0082) -> (17.9113, 74.2005)
  line L2426 (17.9113, 74.2005) -> (17.9065, 74.2985)
  line L2427 (17.9065, 74.2985) -> (17.9065, 75.4985)
  line L2428 (17.9065, 75.4985) -> (17.9113, 75.5965)
  line L2429 (17.9113, 75.5965) -> (17.9496, 75.7888)
  line L2430 (17.9496, 75.7888) -> (18.0246, 75.9699)
  line L2431 (18.0246, 75.9699) -> (18.1335, 76.1329)
  line L2432 (18.1335, 76.1329) -> (18.2721, 76.2715)
  line L2433 (18.2721, 76.2715) -> (18.3065, 76.2945)
  line L2434 (18.3065, 76.2945) -> (18.3065, 78.1422)
  line L2435 (18.3065, 78.1422) -> (17.7369, 78.7118)
  line L2436 (17.7369, 78.7118) -> (17.6852, 78.7708)
  line L2437 (17.6852, 78.7708) -> (17.6068, 78.9065)
  line L2438 (17.6068, 78.9065) -> (17.5663, 79.0578)
  line L2439 (17.5663, 79.0578) -> (17.5612, 79.1361)
  line L2440 (17.5612, 79.1361) -> (17.5612, 83.0649)
  line L2441 (17.5612, 83.0649) -> (17.5663, 83.1432)
  line L2442 (17.5663, 83.1432) -> (17.6068, 83.2945)
  line L2443 (17.6068, 83.2945) -> (17.6852, 83.4302)
  line L2444 (17.6852, 83.4302) -> (17.7369, 83.4892)
  line L2445 (17.7369, 83.4892) -> (22.9274, 88.6796)
  line L2446 (22.9274, 88.6796) -> (22.9274, 89.0733)
  line L2447 (22.9274, 89.0733) -> (22.3024, 89.0733)
  line L2448 (22.3024, 89.0733) -> (22.3024, 92.0733)
  line L2449 (22.3024, 92.0733) -> (24.7524, 92.0733)
  line L2450 (24.7524, 92.0733) -> (24.7524, 89.0733)
  line L2451 (59.6774, 89.0733) -> (59.0524, 89.0733)
  line L2452 (59.0524, 89.0733) -> (59.0524, 88.4311)
  line L2453 (59.0524, 88.4311) -> (59.0472, 88.3528)
  line L2454 (59.0472, 88.3528) -> (59.0067, 88.2015)
  line L2455 (59.0067, 88.2015) -> (58.9284, 88.0658)
  line L2456 (58.9284, 88.0658) -> (58.8766, 88.0068)
  line L2457 (58.8766, 88.0068) -> (53.6862, 82.8164)
  line L2458 (53.6862, 82.8164) -> (53.6862, 79.3846)
  line L2459 (53.6862, 79.3846) -> (54.2558, 78.815)
  line L2460 (54.2558, 78.815) -> (54.3075, 78.756)
  line L2461 (54.3075, 78.756) -> (54.3859, 78.6203)
  line L2462 (54.3859, 78.6203) -> (54.4068, 78.5421)
  line L2463 (54.4068, 78.5421) -> (54.4264, 78.469)
  line L2464 (54.4264, 78.469) -> (54.4315, 78.3907)
  line L2465 (54.4315, 78.3907) -> (54.4315, 76.2945)
  line L2466 (54.4315, 76.2945) -> (54.4659, 76.2715)
  line L2467 (54.4659, 76.2715) -> (54.6045, 76.1329)
  line L2468 (54.6045, 76.1329) -> (54.7134, 75.9699)
  line L2469 (54.7134, 75.9699) -> (54.7885, 75.7888)
  line L2470 (54.7885, 75.7888) -> (54.8267, 75.5965)
  line L2471 (54.8267, 75.5965) -> (54.8315, 75.4985)
  line L2472 (54.8315, 75.4985) -> (54.8315, 74.2985)
  line L2473 (54.8315, 74.2985) -> (54.8267, 74.2005)
  line L2474 (54.8267, 74.2005) -> (54.7885, 74.0082)
  line L2475 (54.7885, 74.0082) -> (54.7134, 73.8271)
  line L2476 (54.7134, 73.8271) -> (54.6045, 73.6641)
  line L2477 (54.6045, 73.6641) -> (54.4659, 73.5255)
  line L2478 (54.4659, 73.5255) -> (54.4315, 73.5025)
  line L2479 (54.4315, 73.5025) -> (54.4315, 59.487)
  line L2480 (54.4315, 59.487) -> (59.0785, 54.84)
  line L2481 (59.0785, 54.84) -> (60.5722, 54.84)
  line L2482 (60.5722, 54.84) -> (60.6814, 54.8241)
  line L2483 (60.6814, 54.8241) -> (60.7946, 54.7687)
  line L2484 (60.7946, 54.7687) -> (60.8837, 54.6796)
  line L2485 (60.8837, 54.6796) -> (60.9391, 54.5664)
  line L2486 (60.9391, 54.5664) -> (60.955, 54.4572)
  line L2487 (60.955, 54.4572) -> (60.955, 52.2228)
  line L2488 (60.955, 52.2228) -> (60.9391, 52.1136)
  line L2489 (60.9391, 52.1136) -> (60.8837, 52.0004)
  line L2490 (60.8837, 52.0004) -> (60.7946, 51.9113)
  line L2491 (60.7946, 51.9113) -> (60.6814, 51.8559)
  line L2492 (60.6814, 51.8559) -> (60.5722, 51.84)
  line L2493 (60.5722, 51.84) -> (58.8878, 51.84)
  line L2494 (58.8878, 51.84) -> (58.7786, 51.8559)
  line L2495 (58.7786, 51.8559) -> (58.6654, 51.9113)
  line L2496 (58.6654, 51.9113) -> (58.5763, 52.0004)
  line L2497 (58.5763, 52.0004) -> (58.5209, 52.1136)
  line L2498 (58.5209, 52.1136) -> (58.505, 52.2228)
  line L2499 (58.505, 52.2228) -> (58.505, 53.7165)
  line L2500 (58.505, 53.7165) -> (53.4073, 58.8142)
  line L2501 (53.4073, 58.8142) -> (53.3555, 58.8732)
  line L2502 (53.3555, 58.8732) -> (53.2772, 59.0089)
  line L2503 (53.2772, 59.0089) -> (53.2367, 59.1602)
  line L2504 (53.2367, 59.1602) -> (53.2315, 59.2385)
  line L2505 (53.2315, 59.2385) -> (53.2315, 73.5025)
  line L2506 (53.2315, 73.5025) -> (53.1971, 73.5255)
  line L2507 (53.1971, 73.5255) -> (53.0585, 73.6641)
  line L2508 (53.0585, 73.6641) -> (52.9496, 73.8271)
  line L2509 (52.9496, 73.8271) -> (52.8746, 74.0082)
  line L2510 (52.8746, 74.0082) -> (52.8363, 74.2005)
  line L2511 (52.8363, 74.2005) -> (52.8315, 74.2985)
  line L2512 (52.8315, 74.2985) -> (52.8315, 75.4985)
  line L2513 (52.8315, 75.4985) -> (52.8363, 75.5965)
  line L2514 (52.8363, 75.5965) -> (52.8746, 75.7888)
  line L2515 (52.8746, 75.7888) -> (52.9496, 75.9699)
  line L2516 (52.9496, 75.9699) -> (53.0585, 76.1329)
  line L2517 (53.0585, 76.1329) -> (53.1971, 76.2715)
  line L2518 (53.1971, 76.2715) -> (53.2315, 76.2945)
  line L2519 (53.2315, 76.2945) -> (53.2315, 78.1422)
  line L2520 (53.2315, 78.1422) -> (52.6619, 78.7118)
  line L2521 (52.6619, 78.7118) -> (52.6102, 78.7708)
  line L2522 (52.6102, 78.7708) -> (52.5318, 78.9065)
  line L2523 (52.5318, 78.9065) -> (52.4913, 79.0578)
  line L2524 (52.4913, 79.0578) -> (52.4862, 79.1361)
  line L2525 (52.4862, 79.1361) -> (52.4862, 83.0649)
  line L2526 (52.4862, 83.0649) -> (52.4913, 83.1432)
  line L2527 (52.4913, 83.1432) -> (52.5318, 83.2945)
  line L2528 (52.5318, 83.2945) -> (52.6102, 83.4302)
  line L2529 (52.6102, 83.4302) -> (52.6619, 83.4892)
  line L2530 (52.6619, 83.4892) -> (57.8524, 88.6796)
  line L2531 (57.8524, 88.6796) -> (57.8524, 89.0733)
  line L2532 (57.8524, 89.0733) -> (57.2274, 89.0733)
  line L2533 (57.2274, 89.0733) -> (57.2274, 92.0733)
  line L2534 (57.2274, 92.0733) -> (59.6774, 92.0733)
  line L2535 (59.6774, 92.0733) -> (59.6774, 89.0733)
  line L2536 (94.6024, 89.0733) -> (93.9774, 89.0733)
  line L2537 (93.9774, 89.0733) -> (93.9774, 88.4311)
  line L2538 (93.9774, 88.4311) -> (93.9722, 88.3528)
  line L2539 (93.9722, 88.3528) -> (93.9317, 88.2015)
  line L2540 (93.9317, 88.2015) -> (93.8534, 88.0658)
  line L2541 (93.8534, 88.0658) -> (93.8016, 88.0068)
  line L2542 (93.8016, 88.0068) -> (88.6112, 82.8164)
  line L2543 (88.6112, 82.8164) -> (88.6112, 79.3846)
  line L2544 (88.6112, 79.3846) -> (89.1808, 78.815)
  line L2545 (89.1808, 78.815) -> (89.2325, 78.756)
  line L2546 (89.2325, 78.756) -> (89.3109, 78.6203)
  line L2547 (89.3109, 78.6203) -> (89.3318, 78.5421)
  line L2548 (89.3318, 78.5421) -> (89.3514, 78.469)
  line L2549 (89.3514, 78.469) -> (89.3565, 78.3907)
  line L2550 (89.3565, 78.3907) -> (89.3565, 76.2945)
  line L2551 (89.3565, 76.2945) -> (89.3909, 76.2715)
  line L2552 (89.3909, 76.2715) -> (89.5295, 76.1329)
  line L2553 (89.5295, 76.1329) -> (89.6384, 75.9699)
  line L2554 (89.6384, 75.9699) -> (89.7135, 75.7888)
  line L2555 (89.7135, 75.7888) -> (89.7517, 75.5965)
  line L2556 (89.7517, 75.5965) -> (89.7565, 75.4985)
  line L2557 (89.7565, 75.4985) -> (89.7565, 74.2985)
  line L2558 (89.7565, 74.2985) -> (89.7517, 74.2005)
  line L2559 (89.7517, 74.2005) -> (89.7135, 74.0082)
  line L2560 (89.7135, 74.0082) -> (89.6384, 73.8271)
  line L2561 (89.6384, 73.8271) -> (89.5295, 73.6641)
  line L2562 (89.5295, 73.6641) -> (89.3909, 73.5255)
  line L2563 (89.3909, 73.5255) -> (89.3565, 73.5025)
  line L2564 (89.3565, 73.5025) -> (89.3565, 59.487)
  line L2565 (89.3565, 59.487) -> (94.0035, 54.84)
  line L2566 (94.0035, 54.84) -> (95.4972, 54.84)
  line L2567 (95.4972, 54.84) -> (95.6064, 54.8241)
  line L2568 (95.6064, 54.8241) -> (95.7196, 54.7687)
  line L2569 (95.7196, 54.7687) -> (95.8087, 54.6796)
  line L2570 (95.8087, 54.6796) -> (95.8641, 54.5664)
  line L2571 (95.8641, 54.5664) -> (95.88, 54.4572)
  line L2572 (95.88, 54.4572) -> (95.88, 52.2228)
  line L2573 (95.88, 52.2228) -> (95.8641, 52.1136)
  line L2574 (95.8641, 52.1136) -> (95.8087, 52.0004)
  line L2575 (95.8087, 52.0004) -> (95.7196, 51.9113)
  line L2576 (95.7196, 51.9113) -> (95.6064, 51.8559)
  line L2577 (95.6064, 51.8559) -> (95.4972, 51.84)
  line L2578 (95.4972, 51.84) -> (93.8128, 51.84)
  line L2579 (93.8128, 51.84) -> (93.7036, 51.8559)
  line L2580 (93.7036, 51.8559) -> (93.5904, 51.9113)
  line L2581 (93.5904, 51.9113) -> (93.5013, 52.0004)
  line L2582 (93.5013, 52.0004) -> (93.4459, 52.1136)
  line L2583 (93.4459, 52.1136) -> (93.43, 52.2228)
  line L2584 (93.43, 52.2228) -> (93.43, 53.7165)
  line L2585 (93.43, 53.7165) -> (88.3323, 58.8142)
  line L2586 (88.3323, 58.8142) -> (88.2805, 58.8732)
  line L2587 (88.2805, 58.8732) -> (88.2022, 59.0089)
  line L2588 (88.2022, 59.0089) -> (88.1617, 59.1602)
  line L2589 (88.1617, 59.1602) -> (88.1565, 59.2385)
  line L2590 (88.1565, 59.2385) -> (88.1565, 73.5025)
  line L2591 (88.1565, 73.5025) -> (88.1221, 73.5255)
  line L2592 (88.1221, 73.5255) -> (87.9835, 73.6641)
  line L2593 (87.9835, 73.6641) -> (87.8746, 73.8271)
  line L2594 (87.8746, 73.8271) -> (87.7996, 74.0082)
  line L2595 (87.7996, 74.0082) -> (87.7613, 74.2005)
  line L2596 (87.7613, 74.2005) -> (87.7565, 74.2985)
  line L2597 (87.7565, 74.2985) -> (87.7565, 75.4985)
  line L2598 (87.7565, 75.4985) -> (87.7613, 75.5965)
  line L2599 (87.7613, 75.5965) -> (87.7996, 75.7888)
  line L2600 (87.7996, 75.7888) -> (87.8746, 75.9699)
  line L2601 (87.8746, 75.9699) -> (87.9835, 76.1329)
  line L2602 (87.9835, 76.1329) -> (88.1221, 76.2715)
  line L2603 (88.1221, 76.2715) -> (88.1565, 76.2945)
  line L2604 (88.1565, 76.2945) -> (88.1565, 78.1422)
  line L2605 (88.1565, 78.1422) -> (87.5869, 78.7118)
  line L2606 (87.5869, 78.7118) -> (87.5352, 78.7708)
  line L2607 (87.5352, 78.7708) -> (87.4568, 78.9065)
  line L2608 (87.4568, 78.9065) -> (87.4163, 79.0578)
  line L2609 (87.4163, 79.0578) -> (87.4112, 79.1361)
  line L2610 (87.4112, 79.1361) -> (87.4112, 83.0649)
  line L2611 (87.4112, 83.0649) -> (87.4163, 83.1432)
  line L2612 (87.4163, 83.1432) -> (87.4568, 83.2945)
  line L2613 (87.4568, 83.2945) -> (87.5352, 83.4302)
  line L2614 (87.5352, 83.4302) -> (87.5869, 83.4892)
  line L2615 (87.5869, 83.4892) -> (92.7774, 88.6796)
  line L2616 (92.7774, 88.6796) -> (92.7774, 89.0733)
  line L2617 (92.7774, 89.0733) -> (92.1524, 89.0733)
  line L2618 (92.1524, 89.0733) -> (92.1524, 92.0733)
  line L2619 (92.1524, 92.0733) -> (94.6024, 92.0733)
  line L2620 (94.6024, 92.0733) -> (94.6024, 89.0733)
  line L2621 (129.5274, 89.0733) -> (128.9024, 89.0733)
  line L2622 (128.9024, 89.0733) -> (128.9024, 88.4311)
  line L2623 (128.9024, 88.4311) -> (128.8972, 88.3528)
  line L2624 (128.8972, 88.3528) -> (128.8567, 88.2015)
  line L2625 (128.8567, 88.2015) -> (128.7784, 88.0658)
  line L2626 (128.7784, 88.0658) -> (128.7266, 88.0068)
  line L2627 (128.7266, 88.0068) -> (123.5362, 82.8164)
  line L2628 (123.5362, 82.8164) -> (123.5362, 79.3846)
  line L2629 (123.5362, 79.3846) -> (124.1058, 78.815)
  line L2630 (124.1058, 78.815) -> (124.1575, 78.756)
  line L2631 (124.1575, 78.756) -> (124.2359, 78.6203)
  line L2632 (124.2359, 78.6203) -> (124.2568, 78.5421)
  line L2633 (124.2568, 78.5421) -> (124.2764, 78.469)
  line L2634 (124.2764, 78.469) -> (124.2815, 78.3907)
  line L2635 (124.2815, 78.3907) -> (124.2815, 76.2945)
  line L2636 (124.2815, 76.2945) -> (124.3159, 76.2715)
  line L2637 (124.3159, 76.2715) -> (124.4545, 76.1329)
  line L2638 (124.4545, 76.1329) -> (124.5634, 75.9699)
  line L2639 (124.5634, 75.9699) -> (124.6385, 75.7888)
  line L2640 (124.6385, 75.7888) -> (124.6767, 75.5965)
  line L2641 (124.6767, 75.5965) -> (124.6815, 75.4985)
  line L2642 (124.6815, 75.4985) -> (124.6815, 74.2985)
  line L2643 (124.6815, 74.2985) -> (124.6767, 74.2005)
  line L2644 (124.6767, 74.2005) -> (124.6385, 74.0082)
  line L2645 (124.6385, 74.0082) -> (124.5634, 73.8271)
  line L2646 (124.5634, 73.8271) -> (124.4545, 73.6641)
  line L2647 (124.4545, 73.6641) -> (124.3159, 73.5255)
  line L2648 (124.3159, 73.5255) -> (124.2815, 73.5025)
  line L2649 (124.2815, 73.5025) -> (124.2815, 59.487)
  line L2650 (124.2815, 59.487) -> (128.9285, 54.84)
  line L2651 (128.9285, 54.84) -> (130.4222, 54.84)
  line L2652 (130.4222, 54.84) -> (130.5314, 54.8241)
  line L2653 (130.5314, 54.8241) -> (130.6446, 54.7687)
  line L2654 (130.6446, 54.7687) -> (130.7337, 54.6796)
  line L2655 (130.7337, 54.6796) -> (130.7891, 54.5664)
  line L2656 (130.7891, 54.5664) -> (130.805, 54.4572)
  line L2657 (130.805, 54.4572) -> (130.805, 52.2228)
  line L2658 (130.805, 52.2228) -> (130.7891, 52.1136)
  line L2659 (130.7891, 52.1136) -> (130.7337, 52.0004)
  line L2660 (130.7337, 52.0004) -> (130.6446, 51.9113)
  line L2661 (130.6446, 51.9113) -> (130.5314, 51.8559)
  line L2662 (130.5314, 51.8559) -> (130.4222, 51.84)
  line L2663 (130.4222, 51.84) -> (128.7378, 51.84)
  line L2664 (128.7378, 51.84) -> (128.6286, 51.8559)
  line L2665 (128.6286, 51.8559) -> (128.5154, 51.9113)
  line L2666 (128.5154, 51.9113) -> (128.4263, 52.0004)
  line L2667 (128.4263, 52.0004) -> (128.3709, 52.1136)
  line L2668 (128.3709, 52.1136) -> (128.355, 52.2228)
  line L2669 (128.355, 52.2228) -> (128.355, 53.7165)
  line L2670 (128.355, 53.7165) -> (123.2573, 58.8142)
  line L2671 (123.2573, 58.8142) -> (123.2055, 58.8732)
  line L2672 (123.2055, 58.8732) -> (123.1272, 59.0089)
  line L2673 (123.1272, 59.0089) -> (123.0867, 59.1602)
  line L2674 (123.0867, 59.1602) -> (123.0815, 59.2385)
  line L2675 (123.0815, 59.2385) -> (123.0815, 73.5025)
  line L2676 (123.0815, 73.5025) -> (123.0471, 73.5255)
  line L2677 (123.0471, 73.5255) -> (122.9085, 73.6641)
  line L2678 (122.9085, 73.6641) -> (122.7996, 73.8271)
  line L2679 (122.7996, 73.8271) -> (122.7246, 74.0082)
  line L2680 (122.7246, 74.0082) -> (122.6863, 74.2005)
  line L2681 (122.6863, 74.2005) -> (122.6815, 74.2985)
  line L2682 (122.6815, 74.2985) -> (122.6815, 75.4985)
  line L2683 (122.6815, 75.4985) -> (122.6863, 75.5965)
  line L2684 (122.6863, 75.5965) -> (122.7246, 75.7888)
  line L2685 (122.7246, 75.7888) -> (122.7996, 75.9699)
  line L2686 (122.7996, 75.9699) -> (122.9085, 76.1329)
  line L2687 (122.9085, 76.1329) -> (123.0471, 76.2715)
  line L2688 (123.0471, 76.2715) -> (123.0815, 76.2945)
  line L2689 (123.0815, 76.2945) -> (123.0815, 78.1422)
  line L2690 (123.0815, 78.1422) -> (122.5119, 78.7118)
  line L2691 (122.5119, 78.7118) -> (122.4602, 78.7708)
  line L2692 (122.4602, 78.7708) -> (122.3818, 78.9065)
  line L2693 (122.3818, 78.9065) -> (122.3413, 79.0578)
  line L2694 (122.3413, 79.0578) -> (122.3362, 79.1361)
  line L2695 (122.3362, 79.1361) -> (122.3362, 83.0649)
  line L2696 (122.3362, 83.0649) -> (122.3413, 83.1432)
  line L2697 (122.3413, 83.1432) -> (122.3818, 83.2945)
  line L2698 (122.3818, 83.2945) -> (122.4602, 83.4302)
  line L2699 (122.4602, 83.4302) -> (122.5119, 83.4892)
  line L2700 (122.5119, 83.4892) -> (127.7024, 88.6796)
  line L2701 (127.7024, 88.6796) -> (127.7024, 89.0733)
  line L2702 (127.7024, 89.0733) -> (127.0774, 89.0733)
  line L2703 (127.0774, 89.0733) -> (127.0774, 92.0733)
  line L2704 (127.0774, 92.0733) -> (129.5274, 92.0733)
  line L2705 (129.5274, 92.0733) -> (129.5274, 89.0733)
  line L2706 (27.0019, 76.3972) -> (27.183, 76.3222)
  line L2707 (27.183, 76.3222) -> (27.346, 76.2133)
  line L2708 (27.346, 76.2133) -> (27.4846, 76.0747)
  line L2709 (27.4846, 76.0747) -> (27.5935, 75.9117)
  line L2710 (27.5935, 75.9117) -> (27.6685, 75.7306)
  line L2711 (27.6685, 75.7306) -> (27.7068, 75.5383)
  line L2712 (27.7068, 75.5383) -> (27.7116, 75.4403)
  line L2713 (27.7116, 75.4403) -> (27.7116, 74.2403)
  line L2714 (27.7116, 74.2403) -> (27.7068, 74.1423)
  line L2715 (27.7068, 74.1423) -> (27.6685, 73.95)
  line L2716 (27.6685, 73.95) -> (27.5935, 73.7689)
  line L2717 (27.5935, 73.7689) -> (27.4846, 73.6059)
  line L2718 (27.4846, 73.6059) -> (27.346, 73.4673)
  line L2719 (27.346, 73.4673) -> (27.3116, 73.4443)
  line L2720 (27.3116, 73.4443) -> (27.3116, 67.3467)
  line L2721 (27.3116, 67.3467) -> (32.188, 62.4703)
  line L2722 (32.188, 62.4703) -> (32.2397, 62.4966)
  line L2723 (32.2397, 62.4966) -> (32.4262, 62.5572)
  line L2724 (32.4262, 62.5572) -> (32.62, 62.5879)
  line L2725 (32.62, 62.5879) -> (32.8161, 62.5879)
  line L2726 (32.8161, 62.5879) -> (33.0098, 62.5572)
  line L2727 (33.0098, 62.5572) -> (33.1964, 62.4966)
  line L2728 (33.1964, 62.4966) -> (33.3712, 62.4075)
  line L2729 (33.3712, 62.4075) -> (33.5299, 62.2922)
  line L2730 (33.5299, 62.2922) -> (33.6686, 62.1536)
  line L2731 (33.6686, 62.1536) -> (33.7838, 61.9949)
  line L2732 (33.7838, 61.9949) -> (33.8729, 61.8201)
  line L2733 (33.8729, 61.8201) -> (33.9335, 61.6335)
  line L2734 (33.9335, 61.6335) -> (33.9642, 61.4398)
  line L2735 (33.9642, 61.4398) -> (33.968, 61.3417)
  line L2736 (33.968, 61.3417) -> (33.968, 60.8417)
  line L2737 (33.968, 60.8417) -> (33.9642, 60.7437)
  line L2738 (33.9642, 60.7437) -> (33.9335, 60.5499)
  line L2739 (33.9335, 60.5499) -> (33.8729, 60.3634)
  line L2740 (33.8729, 60.3634) -> (33.7838, 60.1886)
  line L2741 (33.7838, 60.1886) -> (33.6686, 60.0299)
  line L2742 (33.6686, 60.0299) -> (33.5299, 59.8912)
  line L2743 (33.5299, 59.8912) -> (33.3712, 59.7759)
  line L2744 (33.3712, 59.7759) -> (33.318, 59.7489)
  line L2745 (33.318, 59.7489) -> (33.318, 57.9582)
  line L2746 (33.318, 57.9582) -> (33.3249, 57.9463)
  line L2747 (33.3249, 57.9463) -> (33.3654, 57.795)
  line L2748 (33.3654, 57.795) -> (33.3654, 57.6384)
  line L2749 (33.3654, 57.6384) -> (33.3249, 57.4871)
  line L2750 (33.3249, 57.4871) -> (33.2466, 57.3515)
  line L2751 (33.2466, 57.3515) -> (33.2466, 57.3515)
  line L2752 (33.2466, 57.3515) -> (33.1948, 57.2925)
  line L2753 (33.1948, 57.2925) -> (28.8181, 52.9157)
  line L2754 (28.8181, 52.9157) -> (28.7591, 52.864)
  line L2755 (28.7591, 52.864) -> (28.6235, 52.7857)
  line L2756 (28.6235, 52.7857) -> (28.4864, 52.7489)
  line L2757 (28.4864, 52.7489) -> (28.4368, 52.5962)
  line L2758 (28.4368, 52.5962) -> (28.3495, 52.4249)
  line L2759 (28.3495, 52.4249) -> (28.2365, 52.2694)
  line L2760 (28.2365, 52.2694) -> (28.1006, 52.1335)
  line L2761 (28.1006, 52.1335) -> (27.9451, 52.0205)
  line L2762 (27.9451, 52.0205) -> (27.7738, 51.9332)
  line L2763 (27.7738, 51.9332) -> (27.591, 51.8738)
  line L2764 (27.591, 51.8738) -> (27.4011, 51.8438)
  line L2765 (27.4011, 51.8438) -> (27.2089, 51.8438)
  line L2766 (27.2089, 51.8438) -> (27.019, 51.8738)
  line L2767 (27.019, 51.8738) -> (26.8362, 51.9332)
  line L2768 (26.8362, 51.9332) -> (26.6649, 52.0205)
  line L2769 (26.6649, 52.0205) -> (26.5094, 52.1335)
  line L2770 (26.5094, 52.1335) -> (26.3735, 52.2694)
  line L2771 (26.3735, 52.2694) -> (26.2605, 52.4249)
  line L2772 (26.2605, 52.4249) -> (26.1732, 52.5962)
  line L2773 (26.1732, 52.5962) -> (26.1138, 52.779)
  line L2774 (26.1138, 52.779) -> (26.0838, 52.9689)
  line L2775 (26.0838, 52.9689) -> (26.08, 53.065)
  line L2776 (26.08, 53.065) -> (26.08, 53.615)
  line L2777 (26.08, 53.615) -> (26.0838, 53.7111)
  line L2778 (26.0838, 53.7111) -> (26.1138, 53.901)
  line L2779 (26.1138, 53.901) -> (26.1732, 54.0838)
  line L2780 (26.1732, 54.0838) -> (26.2605, 54.2551)
  line L2781 (26.2605, 54.2551) -> (26.3735, 54.4106)
  line L2782 (26.3735, 54.4106) -> (26.5094, 54.5465)
  line L2783 (26.5094, 54.5465) -> (26.6649, 54.6595)
  line L2784 (26.6649, 54.6595) -> (26.8362, 54.7468)
  line L2785 (26.8362, 54.7468) -> (27.019, 54.8062)
  line L2786 (27.019, 54.8062) -> (27.2089, 54.8362)
  line L2787 (27.2089, 54.8362) -> (27.4011, 54.8362)
  line L2788 (27.4011, 54.8362) -> (27.591, 54.8062)